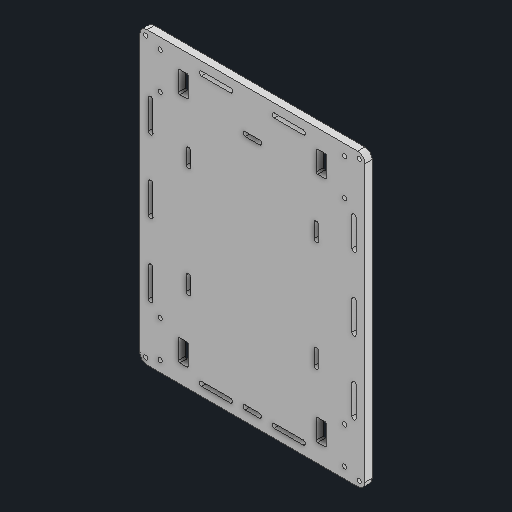
# Autodesk Inventor part: Part3
Saved by Autodesk Inventor 2026.3 (Build 303398000, 398)
## iProperties
Created: 2026-07-17
Part Number: Part3
Material: Generic
Document SubType Name: Modeling
Designer: nose
Density: 1 g/cm^3
Appearance: Default
motor_x_offset: 14.000 mm
motor_y_offset: 20.000 mm
base_width: 155.000 mm
base_length: 200.000 mm
standoff_offset: 4.000 mm
base_fillet: 5.000 mm
Author: nose
Autodesk Inventor part; units mm, degrees
ref_plane "YZ Plane" through (0, 0, 0) normal (1, 0, 0) x (0, 1, 0)
ref_plane "XZ Plane" through (0, 0, 0) normal (0, 1, 0) x (-1, 0, 0)
ref_plane "XY Plane" through (0, 0, 0) normal (0, 0, 1) x (1, 0, 0)
sketch "Sketch1" plane through (0, 0, 0) normal (0, 0, 1) x (1, 0, 0)
  line L0 (72.5, -100) -> (-72.5, -100)
  line L1 (-77.5, -95) -> (-77.5, 95)
  line L2 (-72.5, 100) -> (72.5, 100)
  line L3 (77.5, 95) -> (77.5, -95)
  line L4 (77.5, -100) -> (-77.5, 100) construction
  line L5 (-77.5, -100) -> (77.5, 100) construction
  arc A0 (-72.5, 100) -> (-77.5, 95) centre (-72.5, 95) ccw
  arc A1 (77.5, 95) -> (72.5, 100) centre (72.5, 95) ccw
  arc A2 (72.5, -100) -> (77.5, -95) centre (72.5, -95) ccw
  arc A3 (-77.5, -95) -> (-72.5, -100) centre (-72.5, -95) ccw
  point P0 (0, 0)
  dimension "d0" = 155
  dimension "d1" = 200
  dimension "d26" = 5
  constraints: 12 end point, 8 point on circle, 8 point on line, 8 tangent, 4 centre point, 3 equal radius, 2 midpoint, 2 parallel, 1 horizontal, 1 perpendicular
  measures "d0" distance of L4.end L5.end
  measures "d1" distance of L5.start L4.end
  measures "d26" radius of A0
extrude "base" add sketch "Sketch1" along normal blind 5
sketch "Sketch2" plane through (0, 0, 5) normal (0, 0, 1) x (1, 0, 0)
  circle A0 centre (-63.5, 92.6) radius 1.5
  circle A1 centre (-63.5, 67.4) radius 1.5
  line L0 (-90.3018, 80) -> (-26.5899, 80) construction
  line L1 (-63.5, 59.4965) -> (-63.5, 108.4491) construction
  line L2 (-45, 72.5) -> (-50, 72.5)
  line L3 (-51, 73.5) -> (-51, 86.5)
  line L4 (-50, 87.5) -> (-45, 87.5)
  line L5 (-44, 86.5) -> (-44, 73.5)
  line L6 (-44, 72.5) -> (-51, 87.5) construction
  line L7 (-51, 72.5) -> (-44, 87.5) construction
  arc A2 (-50, 87.5) -> (-51, 86.5) centre (-50, 86.5) ccw
  arc A3 (-44, 86.5) -> (-45, 87.5) centre (-45, 86.5) ccw
  arc A4 (-45, 72.5) -> (-44, 73.5) centre (-45, 73.5) ccw
  arc A5 (-51, 73.5) -> (-50, 72.5) centre (-50, 73.5) ccw
  line L8 (0, -165.9432) -> (0, 165.9432) construction
  line L9 (-120.5021, 0) -> (120.5021, 0) construction
  circle A6 centre (63.5, 92.6) radius 1.5
  circle A7 centre (63.5, 67.4) radius 1.5
  line L10 (45, 72.5) -> (50, 72.5)
  line L11 (51, 73.5) -> (51, 86.5)
  line L12 (50, 87.5) -> (45, 87.5)
  line L13 (44, 86.5) -> (44, 73.5)
  line L14 (44, 72.5) -> (51, 87.5) construction
  line L15 (51, 72.5) -> (44, 87.5) construction
  arc A8 (51, 86.5) -> (50, 87.5) centre (50, 86.5) ccw
  arc A9 (45, 87.5) -> (44, 86.5) centre (45, 86.5) ccw
  arc A10 (44, 73.5) -> (45, 72.5) centre (45, 73.5) ccw
  arc A11 (50, 72.5) -> (51, 73.5) centre (50, 73.5) ccw
  circle A12 centre (-63.5, -92.6) radius 1.5
  circle A13 centre (-63.5, -67.4) radius 1.5
  line L16 (-45, -72.5) -> (-50, -72.5)
  line L17 (-51, -73.5) -> (-51, -86.5)
  line L18 (-50, -87.5) -> (-45, -87.5)
  line L19 (-44, -86.5) -> (-44, -73.5)
  line L20 (-44, -72.5) -> (-51, -87.5) construction
  line L21 (-51, -72.5) -> (-44, -87.5) construction
  arc A14 (-51, -86.5) -> (-50, -87.5) centre (-50, -86.5) ccw
  arc A15 (-45, -87.5) -> (-44, -86.5) centre (-45, -86.5) ccw
  arc A16 (-44, -73.5) -> (-45, -72.5) centre (-45, -73.5) ccw
  arc A17 (-50, -72.5) -> (-51, -73.5) centre (-50, -73.5) ccw
  arc A18 (51, -73.5) -> (50, -72.5) centre (50, -73.5) ccw
  line L22 (45, -72.5) -> (50, -72.5)
  line L23 (51, -73.5) -> (51, -86.5)
  arc A19 (50, -87.5) -> (51, -86.5) centre (50, -86.5) ccw
  line L24 (44, -86.5) -> (44, -73.5)
  line L25 (50, -87.5) -> (45, -87.5)
  line L26 (51, -72.5) -> (44, -87.5) construction
  line L27 (44, -72.5) -> (51, -87.5) construction
  arc A20 (44, -86.5) -> (45, -87.5) centre (45, -86.5) ccw
  arc A21 (45, -72.5) -> (44, -73.5) centre (45, -73.5) ccw
  circle A22 centre (63.5, -67.4) radius 1.5
  circle A23 centre (63.5, -92.6) radius 1.5
  point P0 (0, 0)
  point P1 (-47.5, 80)
  point P2 (-47.5, 72.5)
  point P3 (63.5, 59.4965)
  point P4 (47.5, 80)
  point P5 (47.5, 72.5)
  point P6 (-26.5899, -80)
  point P7 (-47.5, -80)
  point P8 (-47.5, -72.5)
  point P9 (47.5, -72.5)
  point P10 (47.5, -80)
  dimension "d4" = 3
  dimension "d5" = 1
  dimension "d6" = 1
  dimension "d7" = 1
  dimension "d8" = 1
  dimension "d9" = 15
  dimension "d10" = 7
  dimension "d11" = 7
  dimension "d12" = 63.5
  dimension "d13" = 80
  dimension "d14" = 1
  dimension "d15" = 1
  dimension "d16" = 1
  constraints: 62 symmetric about line, 56 end point, 35 point on line, 32 point on circle, 24 centre point, 8 tangent, 5 midpoint, 3 horizontal, 2 parallel, 2 vertical, 1 perpendicular, 18 other
  measures "d4" diameter of A0
  measures "d10" distance of L6.end L7.end
  measures "d14" radius of A3
  measures "d15" radius of A4
  measures "d16" radius of A5
extrude "motor_mount" cut sketch "Sketch2" against normal through all
sketch "Sketch4" plane through (0, 0, 5) normal (0, 0, 1) x (1, 0, 0)
  circle A0 centre (-73.5, 96) radius 1.5
  line L0 (0, -163.8328) -> (0, 163.8328) construction
  line L1 (-154.6878, 0) -> (154.6878, 0) construction
  circle A1 centre (73.5, 96) radius 1.5
  circle A2 centre (-73.5, -96) radius 1.5
  circle A3 centre (73.5, -96) radius 1.5
  point P0 (0, 0)
  dimension "d21" = 3
  dimension "d22" = 96
  dimension "d23" = 73.5
  constraints: 4 centre point, 4 end point, 3 symmetric about line, 2 midpoint, 1 horizontal, 1 vertical, 3 other
  measures "d21" diameter of A0
  measures "d22" vertical distance of point (0, 0) A0.centre
  measures "d23" horizontal distance of point (0, 0) A0.centre
extrude "standoff_mount" cut sketch "Sketch4" against normal through all
sketch "Sketch5" plane through (0, 0, 5) normal (0, 0, 1) x (1, 0, 0)
  line L0 (-42.5, 70) -> (42.5, 70) construction
  line L1 (42.5, 70) -> (42.5, -90) construction
  line L2 (42.5, -90) -> (-42.5, -90) construction
  line L3 (-42.5, -90) -> (-42.5, 70) construction
  line L4 (-44, -58.2465) -> (-44, 58.2465) construction
  line L5 (-44, 42.7663) -> (-44, 32.7663) construction
  line L6 (-45.5, 42.7663) -> (-45.5, 32.7663)
  line L7 (-42.5, 32.7663) -> (-42.5, 42.7663)
  arc A0 (-42.5, 42.7663) -> (-45.5, 42.7663) centre (-44, 42.7663) ccw
  arc A1 (-45.5, 32.7663) -> (-42.5, 32.7663) centre (-44, 32.7663) ccw
  line L8 (0, -177.0777) -> (0, 177.0777) construction
  line L9 (-133.1759, 0) -> (133.1759, 0) construction
  line L10 (44, 42.7663) -> (44, 32.7663) construction
  line L11 (45.5, 42.7663) -> (45.5, 32.7663)
  line L12 (42.5, 32.7663) -> (42.5, 42.7663)
  arc A2 (45.5, 42.7663) -> (42.5, 42.7663) centre (44, 42.7663) ccw
  arc A3 (42.5, 32.7663) -> (45.5, 32.7663) centre (44, 32.7663) ccw
  line L13 (-44, -42.7663) -> (-44, -32.7663) construction
  line L14 (-45.5, -42.7663) -> (-45.5, -32.7663)
  line L15 (-42.5, -32.7663) -> (-42.5, -42.7663)
  arc A4 (-45.5, -42.7663) -> (-42.5, -42.7663) centre (-44, -42.7663) ccw
  arc A5 (-42.5, -32.7663) -> (-45.5, -32.7663) centre (-44, -32.7663) ccw
  arc A6 (45.5, -32.7663) -> (42.5, -32.7663) centre (44, -32.7663) ccw
  line L16 (42.5, -32.7663) -> (42.5, -42.7663)
  line L17 (44, -42.7663) -> (44, -32.7663) construction
  line L18 (45.5, -42.7663) -> (45.5, -32.7663)
  arc A7 (42.5, -42.7663) -> (45.5, -42.7663) centre (44, -42.7663) ccw
  line L19 (-82.421, 71.5) -> (90.579, 71.5) construction
  line L20 (-5, 71.5) -> (5, 71.5) construction
  line L21 (-5, 70) -> (5, 70)
  line L22 (5, 73) -> (-5, 73)
  arc A8 (-5, 73) -> (-5, 70) centre (-5, 71.5) ccw
  arc A9 (5, 70) -> (5, 73) centre (5, 71.5) ccw
  line L23 (-5, -91.5) -> (5, -91.5) construction
  line L24 (-5, -93) -> (5, -93)
  line L25 (5, -90) -> (-5, -90)
  arc A10 (-5, -90) -> (-5, -93) centre (-5, -91.5) ccw
  arc A11 (5, -93) -> (5, -90) centre (5, -91.5) ccw
  point P0 (0, 0)
  point P1 (-44, 37.7663)
  point P2 (44, 37.7663)
  point P3 (-44, -37.7663)
  point P4 (44, -37.7663)
  point P5 (0, 71.5)
  point P6 (0, -91.5)
  dimension "d27" = 155
  dimension "d28" = 14
  dimension "d29" = 200
  dimension "d30" = 20
  dimension "d31" = 4
  dimension "d32" = 49
  dimension "d33" = 58
  dimension "d34" = 2.5
  dimension "d35" = 2.5
  dimension "d36" = 2.5
  dimension "d39" = 163
  constraints: 64 end point, 24 point on circle, 21 symmetric about line, 12 centre point, 8 tangent, 5 parallel, 5 point on line, 4 midpoint, 3 horizontal, 2 vertical, 1 perpendicular, 18 other
  measures "d39" distance of L21.start L24.start
extrude "powerbank_slot" cut sketch "Sketch5" against normal through all
sketch "Sketch6" plane through (0, 0.0245, 5) normal (0, 0, 1) x (1, 0, 0)
  line L0 (-70, -10) -> (-70, 10) construction
  line L1 (-68.5, -10) -> (-68.5, 10)
  line L2 (-71.5, 10) -> (-71.5, -10)
  arc A0 (-71.5, -10) -> (-68.5, -10) centre (-70, -10) ccw
  arc A1 (-68.5, 10) -> (-71.5, 10) centre (-70, 10) ccw
  line L3 (-70, -100) -> (-70, 100) construction
  line L4 (72.5, 100) -> (-72.5, 100)
  line L5 (-77.5, 95) -> (-77.5, -95)
  line L6 (-70, 40) -> (-70, 60) construction
  line L7 (-68.5, 40) -> (-68.5, 60)
  line L8 (-71.5, 60) -> (-71.5, 40)
  arc A2 (-71.5, 40) -> (-68.5, 40) centre (-70, 40) ccw
  arc A3 (-68.5, 60) -> (-71.5, 60) centre (-70, 60) ccw
  line L9 (-70, -59.218) -> (-70, 159.218) construction
  line L10 (-70, -60) -> (-70, -40) construction
  line L11 (-68.5, -60) -> (-68.5, -40)
  line L12 (-71.5, -40) -> (-71.5, -60)
  arc A4 (-71.5, -60) -> (-68.5, -60) centre (-70, -60) ccw
  arc A5 (-68.5, -40) -> (-71.5, -40) centre (-70, -40) ccw
  line L13 (-70, -139.2071) -> (-70, 39.2071) construction
  line L14 (-128.024, 0) -> (128.024, 0) construction
  line L15 (0, -161.5039) -> (0, 161.5039) construction
  line L16 (128.024, 0) -> (-128.024, 0) construction
  arc A6 (71.5, 60) -> (68.5, 60) centre (70, 60) ccw
  line L17 (68.5, 40) -> (68.5, 60)
  line L18 (70, 40) -> (70, 60) construction
  line L19 (71.5, 60) -> (71.5, 40)
  arc A7 (68.5, 40) -> (71.5, 40) centre (70, 40) ccw
  line L20 (68.5, -10) -> (68.5, 10)
  arc A8 (68.5, -10) -> (71.5, -10) centre (70, -10) ccw
  line L21 (70, -59.218) -> (70, 159.218) construction
  line L22 (70, -100) -> (70, 100) construction
  arc A9 (71.5, -40) -> (68.5, -40) centre (70, -40) ccw
  arc A10 (68.5, -60) -> (71.5, -60) centre (70, -60) ccw
  arc A11 (71.5, 10) -> (68.5, 10) centre (70, 10) ccw
  line L23 (70, -10) -> (70, 10) construction
  line L24 (71.5, 10) -> (71.5, -10)
  line L25 (70, -139.2071) -> (70, 39.2071) construction
  line L26 (71.5, -40) -> (71.5, -60)
  line L27 (70, -60) -> (70, -40) construction
  line L28 (68.5, -60) -> (68.5, -40)
  line L29 (77.5, 92.5) -> (-77.5, 92.5) construction
  line L30 (-35, 92.5) -> (-15, 92.5) construction
  line L31 (-35, 91) -> (-15, 91)
  line L32 (-15, 94) -> (-35, 94)
  arc A12 (-35, 94) -> (-35, 91) centre (-35, 92.5) ccw
  arc A13 (-15, 91) -> (-15, 94) centre (-15, 92.5) ccw
  line L33 (15, 92.5) -> (35, 92.5) construction
  line L34 (15, 91) -> (35, 91)
  line L35 (35, 94) -> (15, 94)
  arc A14 (15, 94) -> (15, 91) centre (15, 92.5) ccw
  arc A15 (35, 91) -> (35, 94) centre (35, 92.5) ccw
  arc A16 (-35, -91) -> (-35, -94) centre (-35, -92.5) ccw
  line L36 (-35, -91) -> (-15, -91)
  line L37 (-35, -92.5) -> (-15, -92.5) construction
  line L38 (-15, -94) -> (-35, -94)
  arc A17 (-15, -94) -> (-15, -91) centre (-15, -92.5) ccw
  arc A18 (15, -91) -> (15, -94) centre (15, -92.5) ccw
  line L39 (15, -91) -> (35, -91)
  line L40 (15, -92.5) -> (35, -92.5) construction
  line L41 (35, -94) -> (15, -94)
  arc A19 (35, -94) -> (35, -91) centre (35, -92.5) ccw
  point P0 (0, 0)
  point P1 (-70, 0)
  point P2 (-70, 50)
  point P3 (-70, -50)
  point P4 (70, 50)
  point P5 (70, 0)
  point P6 (70, -50)
  point P7 (0, 92.5)
  point P8 (-25, 92.5)
  point P9 (25, 92.5)
  point P10 (-25, -92.5)
  point P11 (0, -92.5)
  point P12 (25, -92.5)
  dimension "d61" = 10
  dimension "d60" = 7.5
  dimension "d59" = 50
  dimension "d58" = 50
  dimension "d56" = 3
  dimension "d55" = 10
  dimension "d53" = 10
  dimension "d57" = 50
  dimension "d54" = 3
  dimension "d52" = 7.5
  dimension "d51" = 3
  dimension "d49" = 3
  dimension "d48" = 25
  dimension "d46" = 20
  dimension "d47" = 30
  dimension "d50" = 10
  constraints: 104 end point, 44 symmetric about line, 40 point on circle, 20 centre point, 20 tangent, 13 point on line, 11 midpoint, 7 vertical, 5 parallel, 1 horizontal, 1 perpendicular, 10 other
  measures "d61" distance of point (-70, 0) L0.end
  measures "d56" diameter of A3
  measures "d55" distance of point (-70, -50) L10.end
  measures "d57" distance of point (-70, 50) point (-70, 0)
  measures "d52" distance between parallel lines of L29 L4
  measures "d49" diameter of A13
extrude "screw_mouting" cut sketch "Sketch6" against normal through all
equation "\"d0\" = base_width"
equation "\"d1\" = base_length"
equation "\"d26\" = base_fillet"
equation "\"d2\" = base_fillet"
equation "\"d12\" = 0.5 * d27 - d28"
equation "\"d13\" = 0.5 * d29 - d30"
equation "\"d22\" = 0.5 * d29 - d31"
equation "\"d23\" = 0.5 * d27 - d31"
equation "\"d32\" = rpi_hole_width"
equation "\"d33\" = rpi_hole_length"
equation "\"d34\" = rpi_hole_dia"
equation "\"d35\" = rpi_hole_dia"
equation "\"d36\" = rpi_hole_dia"
equation "\"d61\" = screw_mouting_length"
equation "\"d60\" = screw_mouting_edge_offset"
equation "\"d59\" = screw_mouting_y_offset"
equation "\"d58\" = screw_mouting_y_offset"
equation "\"d56\" = screw_mouting_dia"
equation "\"d55\" = screw_mouting_length"
equation "\"d53\" = screw_mouting_length"
equation "\"d57\" = d69"
equation "\"d54\" = screw_mouting_dia"
equation "\"d52\" = screw_mouting_edge_offset"
equation "\"d51\" = screw_mouting_dia"
equation "\"d49\" = d65"
equation "\"d48\" = d67"
equation "\"d50\" = screw_mouting_length"
equation "\"motor_x_offset\" = 14"
equation "\"motor_y_offset\" = 20"
equation "\"base_width\" = 155"
equation "\"base_length\" = 200"
equation "\"standoff_offset\" = 4"
equation "\"base_fillet\" = 5"
equation "\"d67\" = screw_mouting_x_offset"
equation "\"d19\" = 0"
equation "\"rpi_hole_width\" = 49"
equation "\"rpi_hole_length\" = 58"
equation "\"rpi_hole_dia\" = 2.5"
equation "\"d40\" = 15"
equation "\"d41\" = 12.5"
equation "\"d44\" = 12.5"
equation "\"screw_mouting_x_offset\" = 25"
equation "\"screw_mouting_dia\" = 3"
equation "\"screw_mouting_length\" = 10"
equation "\"screw_mouting_edge_offset\" = 7.5"
equation "\"d62\" = screw_mouting_dia"
equation "\"d64\" = screw_mouting_dia"
equation "\"screw_mouting_y_offset\" = 50"
equation "\"d65\" = 3"
equation "\"d69\" = 50"
body "Solid1"
